Autodesk Fusion 360 part; units mm, degrees
(part 2 of 2)
ref_plane "WorkPlane7" through (0, 0, 8) normal (0, 0, 1) x (1, 0, 0) in component "07 Doorframe mounting platform - PRINT"
sketch "Case locating tab 2 outline" plane through (0, 0, 8) normal (0, 0, 1) x (1, 0, 0) in component "07 Doorframe mounting platform - PRINT"
  line L0 (112, 48.6) -> (132, 48.6)
  line L1 (132, 48.6) -> (132, 50)
  line L2 (132, 50) -> (112, 50)
  line L3 (112, 50) -> (112, 48.6)
extrude "Case locating tab 2" add sketch "Case locating tab 2 outline" along normal blind 6 bodies 22 in component "07 Doorframe mounting platform - PRINT"
ref_plane "WorkPlane8" through (0, 0, 8) normal (0, 0, 1) x (1, 0, 0) in component "07 Doorframe mounting platform - PRINT"
sketch "Case locating tab 3 outline" plane through (0, 0, 8) normal (0, 0, 1) x (1, 0, 0) in component "07 Doorframe mounting platform - PRINT"
  line L0 (10, -41.6) -> (30, -41.6)
  line L1 (30, -41.6) -> (30, -40.4)
  line L2 (30, -40.4) -> (10, -40.4)
  line L3 (10, -40.4) -> (10, -41.6)
extrude "Case locating tab 3" add sketch "Case locating tab 3 outline" along normal blind 6 bodies 22 in component "07 Doorframe mounting platform - PRINT"
ref_plane "WorkPlane9" through (0, 0, 8) normal (0, 0, 1) x (1, 0, 0) in component "07 Doorframe mounting platform - PRINT"
sketch "Case locating tab 4 outline" plane through (0, 0, 8) normal (0, 0, 1) x (1, 0, 0) in component "07 Doorframe mounting platform - PRINT"
  line L0 (112, -41.6) -> (132, -41.6)
  line L1 (132, -41.6) -> (132, -40.4)
  line L2 (132, -40.4) -> (112, -40.4)
  line L3 (112, -40.4) -> (112, -41.6)
extrude "Case locating tab 4" add sketch "Case locating tab 4 outline" along normal blind 6 bodies 22 in component "07 Doorframe mounting platform - PRINT"
ref_plane "WorkPlane10" through (0, 0, 8) normal (0, 0, 1) x (1, 0, 0) in component "07 Doorframe mounting platform - PRINT"
sketch "Case locating tab 5 outline" plane through (0, 0, 8) normal (0, 0, 1) x (1, 0, 0) in component "07 Doorframe mounting platform - PRINT"
  line L0 (-1.6, -30) -> (-0.4, -30)
  line L1 (-0.4, -30) -> (-0.4, -20)
  line L2 (-0.4, -20) -> (-1.6, -20)
  line L3 (-1.6, -20) -> (-1.6, -30)
extrude "Case locating tab 5" add sketch "Case locating tab 5 outline" along normal blind 6 bodies 22 in component "07 Doorframe mounting platform - PRINT"
ref_plane "WorkPlane11" through (0, 0, 8) normal (0, 0, 1) x (1, 0, 0) in component "07 Doorframe mounting platform - PRINT"
sketch "Case locating tab 6 outline" plane through (0, 0, 8) normal (0, 0, 1) x (1, 0, 0) in component "07 Doorframe mounting platform - PRINT"
  line L0 (-1.6, 28) -> (-0.4, 28)
  line L1 (-0.4, 28) -> (-0.4, 38)
  line L2 (-0.4, 38) -> (-1.6, 38)
  line L3 (-1.6, 38) -> (-1.6, 28)
extrude "Case locating tab 6" add sketch "Case locating tab 6 outline" along normal blind 6 bodies 22 in component "07 Doorframe mounting platform - PRINT"
ref_plane "WorkPlane12" through (0, 0, 8) normal (0, 0, 1) x (1, 0, 0) in component "07 Doorframe mounting platform - PRINT"
sketch "Case locating tab 7 outline" plane through (0, 0, 8) normal (0, 0, 1) x (1, 0, 0) in component "07 Doorframe mounting platform - PRINT"
  line L0 (142.4, -30) -> (143.6, -30)
  line L1 (143.6, -30) -> (143.6, -20)
  line L2 (143.6, -20) -> (142.4, -20)
  line L3 (142.4, -20) -> (142.4, -30)
extrude "Case locating tab 7" add sketch "Case locating tab 7 outline" along normal blind 6 bodies 22 in component "07 Doorframe mounting platform - PRINT"
ref_plane "WorkPlane13" through (0, 0, 8) normal (0, 0, 1) x (1, 0, 0) in component "07 Doorframe mounting platform - PRINT"
sketch "Case locating tab 8 outline" plane through (0, 0, 8) normal (0, 0, 1) x (1, 0, 0) in component "07 Doorframe mounting platform - PRINT"
  line L0 (142.4, 28) -> (143.6, 28)
  line L1 (143.6, 28) -> (143.6, 38)
  line L2 (143.6, 38) -> (142.4, 38)
  line L3 (142.4, 38) -> (142.4, 28)
extrude "Case locating tab 8" add sketch "Case locating tab 8 outline" along normal blind 6 bodies 22 in component "07 Doorframe mounting platform - PRINT"
ref_plane "WorkPlane14" through (0, 0, 1.9) normal (0, 0, 1) x (1, 0, 0) in component "07 Doorframe mounting platform - PRINT"
sketch "M4 long clamp bolt clearance layout" plane through (0, 0, 1.9) normal (0, 0, 1) x (1, 0, 0) in component "07 Doorframe mounting platform - PRINT"
  circle A0 centre (-10, -24) radius 2.25
  circle A1 centre (152, -24) radius 2.25
extrude "M4 long clamp bolt clearance" cut sketch "M4 long clamp bolt clearance layout" along normal blind 6.2 bodies 22 in component "07 Doorframe mounting platform - PRINT"
ref_plane "WorkPlane15" through (0, 0, 1.9) normal (0, 0, 1) x (1, 0, 0) in component "07 Doorframe mounting platform - PRINT"
sketch "M3 guide attachment clearance layout" plane through (0, 0, 1.9) normal (0, 0, 1) x (1, 0, 0) in component "07 Doorframe mounting platform - PRINT"
  circle A0 centre (-15, -8.5) radius 1.7
  circle A1 centre (-5, -8.5) radius 1.7
  circle A2 centre (147, -8.5) radius 1.7
  circle A3 centre (157, -8.5) radius 1.7
extrude "M3 guide attachment clearance" cut sketch "M3 guide attachment clearance layout" along normal blind 6.2 bodies 22 in component "07 Doorframe mounting platform - PRINT"
ref_plane "WorkPlane16" through (0, 0, 1.9) normal (0, 0, 1) x (1, 0, 0) in component "07 Doorframe mounting platform - PRINT"
sketch "Top-ledge rubber pad recesses layout" plane through (0, 0, 1.9) normal (0, 0, 1) x (1, 0, 0) in component "07 Doorframe mounting platform - PRINT"
  line L0 (-21, 2) -> (-1, 2)
  line L1 (-1, 2) -> (-1, 16)
  line L2 (-1, 16) -> (-21, 16)
  line L3 (-21, 16) -> (-21, 2)
  line L4 (-21, 33) -> (-1, 33)
  line L5 (-1, 33) -> (-1, 47)
  line L6 (-1, 47) -> (-21, 47)
  line L7 (-21, 47) -> (-21, 33)
  line L8 (143, 2) -> (163, 2)
  line L9 (163, 2) -> (163, 16)
  line L10 (163, 16) -> (143, 16)
  line L11 (143, 16) -> (143, 2)
  line L12 (143, 33) -> (163, 33)
  line L13 (163, 33) -> (163, 47)
  line L14 (163, 47) -> (143, 47)
  line L15 (143, 47) -> (143, 33)
extrude "Top-ledge rubber pad recesses" cut sketch "Top-ledge rubber pad recesses layout" along normal blind 0.6 bodies 22 in component "07 Doorframe mounting platform - PRINT"
ref_plane "WorkPlane1" through (0, 0, -53) normal (0, 0, 1) x (1, 0, 0) in component "08 left clamp guide - PRINT"
sketch "Guide beam outline" plane through (0, 0, -53) normal (0, 0, 1) x (1, 0, 0) in component "08 left clamp guide - PRINT"
  line L0 (-20, -11) -> (0, -11)
  line L1 (0, -11) -> (0, -6)
  line L2 (0, -6) -> (-20, -6)
  line L3 (-20, -6) -> (-20, -11)
extrude "Guide beam" add sketch "Guide beam outline" along normal blind 52 separate body makes body 23 in component "08 left clamp guide - PRINT"
ref_plane "WorkPlane2" through (0, 0, -1) normal (0, 0, 1) x (1, 0, 0) in component "08 left clamp guide - PRINT"
sketch "Guide mounting flange outline" plane through (0, 0, -1) normal (0, 0, 1) x (1, 0, 0) in component "08 left clamp guide - PRINT"
  line L0 (-23, -14) -> (3, -14)
  line L1 (3, -14) -> (3, -3)
  line L2 (3, -3) -> (-23, -3)
  line L3 (-23, -3) -> (-23, -14)
extrude "Guide mounting flange" add sketch "Guide mounting flange outline" along normal blind 3 bodies 23 in component "08 left clamp guide - PRINT"
ref_plane "WorkPlane3" through (0, 0, 2.1) normal (0, 0, 1) x (1, 0, 0) in component "08 left clamp guide - PRINT"
sketch "Two M3 guide pilots layout" plane through (0, 0, 2.1) normal (0, 0, 1) x (1, 0, 0) in component "08 left clamp guide - PRINT"
  circle A0 centre (-15, -8.5) radius 1.25
  circle A1 centre (-5, -8.5) radius 1.25
extrude "Two M3 guide pilots" cut sketch "Two M3 guide pilots layout" against normal blind 7.1 bodies 23 in component "08 left clamp guide - PRINT"
ref_plane "WorkPlane1" through (0, 0, -62) normal (0, 0, 1) x (1, 0, 0) in component "09 left sliding clamp jaw - PRINT"
sketch "Lower clamping jaw outline" plane through (0, 0, -62) normal (0, 0, 1) x (1, 0, 0) in component "09 left sliding clamp jaw - PRINT"
  line L0 (-23.35, -29) -> (3.35, -29)
  line L1 (3.35, -29) -> (3.35, 11.2)
  line L2 (3.35, 11.2) -> (-23.35, 11.2)
  line L3 (-23.35, 11.2) -> (-23.35, -29)
extrude "Lower clamping jaw" add sketch "Lower clamping jaw outline" along normal blind 5 separate body makes body 24 in component "09 left sliding clamp jaw - PRINT"
ref_plane "WorkPlane2" through (0, 0, -57) normal (0, 0, 1) x (1, 0, 0) in component "09 left sliding clamp jaw - PRINT"
sketch "Antirotation guide sleeve outline" plane through (0, 0, -57) normal (0, 0, 1) x (1, 0, 0) in component "09 left sliding clamp jaw - PRINT"
  line L0 (-23.35, -14.35) -> (3.35, -14.35)
  line L1 (3.35, -14.35) -> (3.35, -2.65)
  line L2 (3.35, -2.65) -> (-23.35, -2.65)
  line L3 (-23.35, -2.65) -> (-23.35, -14.35)
extrude "Antirotation guide sleeve" add sketch "Antirotation guide sleeve outline" along normal blind 16 bodies 24 in component "09 left sliding clamp jaw - PRINT"
ref_plane "WorkPlane3" through (0, 0, -57) normal (0, 0, 1) x (1, 0, 0) in component "09 left sliding clamp jaw - PRINT"
sketch "Sliding guide clearance outline" plane through (0, 0, -57) normal (0, 0, 1) x (1, 0, 0) in component "09 left sliding clamp jaw - PRINT"
  line L0 (-20.35, -11.35) -> (0.35, -11.35)
  line L1 (0.35, -11.35) -> (0.35, -5.65)
  line L2 (0.35, -5.65) -> (-20.35, -5.65)
  line L3 (-20.35, -5.65) -> (-20.35, -11.35)
extrude "Sliding guide clearance" cut sketch "Sliding guide clearance outline" along normal blind 16.1 bodies 24 in component "09 left sliding clamp jaw - PRINT"
ref_plane "WorkPlane4" through (0, 0, -62.1) normal (0, 0, 1) x (1, 0, 0) in component "09 left sliding clamp jaw - PRINT"
sketch "M4 long bolt clearance layout" plane through (0, 0, -62.1) normal (0, 0, 1) x (1, 0, 0) in component "09 left sliding clamp jaw - PRINT"
  circle A0 centre (-10, -24) radius 2.25
extrude "M4 long bolt clearance" cut sketch "M4 long bolt clearance layout" along normal blind 5.2 bodies 24 in component "09 left sliding clamp jaw - PRINT"
ref_plane "WorkPlane5" through (0, 0, -62.1) normal (0, 0, 1) x (1, 0, 0) in component "09 left sliding clamp jaw - PRINT"
sketch "Captive M4 nut outline" plane through (0, 0, -62.1) normal (0, 0, 1) x (1, 0, 0) in component "09 left sliding clamp jaw - PRINT"
  line L0 (-5.8431, -24) -> (-7.9215, -20.4)
  line L1 (-7.9215, -20.4) -> (-12.0785, -20.4)
  line L2 (-12.0785, -20.4) -> (-14.1569, -24)
  line L3 (-14.1569, -24) -> (-12.0785, -27.6)
  line L4 (-12.0785, -27.6) -> (-7.9215, -27.6)
  line L5 (-7.9215, -27.6) -> (-5.8431, -24)
extrude "Captive M4 nut" cut sketch "Captive M4 nut outline" along normal blind 3.5 bodies 24 in component "09 left sliding clamp jaw - PRINT"
ref_plane "WorkPlane6" through (0, 0, -57.5) normal (0, 0, 1) x (1, 0, 0) in component "09 left sliding clamp jaw - PRINT"
sketch "Jaw rubber pad recess layout" plane through (0, 0, -57.5) normal (0, 0, 1) x (1, 0, 0) in component "09 left sliding clamp jaw - PRINT"
  line L0 (-18, 1.5) -> (-2, 1.5)
  line L1 (-2, 1.5) -> (-2, 10.5)
  line L2 (-2, 10.5) -> (-18, 10.5)
  line L3 (-18, 10.5) -> (-18, 1.5)
extrude "Jaw rubber pad recess" cut sketch "Jaw rubber pad recess layout" along normal blind 0.6 bodies 24 in component "09 left sliding clamp jaw - PRINT"
ref_plane "WorkPlane1" through (0, 0, -53) normal (0, 0, 1) x (1, 0, 0) in component "08 right clamp guide - PRINT"
sketch "Guide beam outline (2)" plane through (0, 0, -53) normal (0, 0, 1) x (1, 0, 0) in component "08 right clamp guide - PRINT"
  line L0 (142, -11) -> (162, -11)
  line L1 (162, -11) -> (162, -6)
  line L2 (162, -6) -> (142, -6)
  line L3 (142, -6) -> (142, -11)
extrude "Guide beam'" add sketch "Guide beam outline (2)" along normal blind 52 separate body makes body 25 in component "08 right clamp guide - PRINT"
ref_plane "WorkPlane2" through (0, 0, -1) normal (0, 0, 1) x (1, 0, 0) in component "08 right clamp guide - PRINT"
sketch "Guide mounting flange outline (2)" plane through (0, 0, -1) normal (0, 0, 1) x (1, 0, 0) in component "08 right clamp guide - PRINT"
  line L0 (139, -14) -> (165, -14)
  line L1 (165, -14) -> (165, -3)
  line L2 (165, -3) -> (139, -3)
  line L3 (139, -3) -> (139, -14)
extrude "Guide mounting flange'" add sketch "Guide mounting flange outline (2)" along normal blind 3 bodies 25 in component "08 right clamp guide - PRINT"
ref_plane "WorkPlane3" through (0, 0, 2.1) normal (0, 0, 1) x (1, 0, 0) in component "08 right clamp guide - PRINT"
sketch "Two M3 guide pilots layout (2)" plane through (0, 0, 2.1) normal (0, 0, 1) x (1, 0, 0) in component "08 right clamp guide - PRINT"
  circle A0 centre (147, -8.5) radius 1.25
  circle A1 centre (157, -8.5) radius 1.25
extrude "Two M3 guide pilots'" cut sketch "Two M3 guide pilots layout (2)" against normal blind 7.1 bodies 25 in component "08 right clamp guide - PRINT"
ref_plane "WorkPlane1" through (0, 0, -62) normal (0, 0, 1) x (1, 0, 0) in component "09 right sliding clamp jaw - PRINT"
sketch "Lower clamping jaw outline (2)" plane through (0, 0, -62) normal (0, 0, 1) x (1, 0, 0) in component "09 right sliding clamp jaw - PRINT"
  line L0 (138.65, -29) -> (165.35, -29)
  line L1 (165.35, -29) -> (165.35, 11.2)
  line L2 (165.35, 11.2) -> (138.65, 11.2)
  line L3 (138.65, 11.2) -> (138.65, -29)
extrude "Lower clamping jaw'" add sketch "Lower clamping jaw outline (2)" along normal blind 5 separate body makes body 26 in component "09 right sliding clamp jaw - PRINT"
ref_plane "WorkPlane2" through (0, 0, -57) normal (0, 0, 1) x (1, 0, 0) in component "09 right sliding clamp jaw - PRINT"
sketch "Antirotation guide sleeve outline (2)" plane through (0, 0, -57) normal (0, 0, 1) x (1, 0, 0) in component "09 right sliding clamp jaw - PRINT"
  line L0 (138.65, -14.35) -> (165.35, -14.35)
  line L1 (165.35, -14.35) -> (165.35, -2.65)
  line L2 (165.35, -2.65) -> (138.65, -2.65)
  line L3 (138.65, -2.65) -> (138.65, -14.35)
extrude "Antirotation guide sleeve'" add sketch "Antirotation guide sleeve outline (2)" along normal blind 16 bodies 26 in component "09 right sliding clamp jaw - PRINT"
ref_plane "WorkPlane3" through (0, 0, -57) normal (0, 0, 1) x (1, 0, 0) in component "09 right sliding clamp jaw - PRINT"
sketch "Sliding guide clearance outline (2)" plane through (0, 0, -57) normal (0, 0, 1) x (1, 0, 0) in component "09 right sliding clamp jaw - PRINT"
  line L0 (141.65, -11.35) -> (162.35, -11.35)
  line L1 (162.35, -11.35) -> (162.35, -5.65)
  line L2 (162.35, -5.65) -> (141.65, -5.65)
  line L3 (141.65, -5.65) -> (141.65, -11.35)
extrude "Sliding guide clearance'" cut sketch "Sliding guide clearance outline (2)" along normal blind 16.1 bodies 26 in component "09 right sliding clamp jaw - PRINT"
ref_plane "WorkPlane4" through (0, 0, -62.1) normal (0, 0, 1) x (1, 0, 0) in component "09 right sliding clamp jaw - PRINT"
sketch "M4 long bolt clearance layout (2)" plane through (0, 0, -62.1) normal (0, 0, 1) x (1, 0, 0) in component "09 right sliding clamp jaw - PRINT"
  circle A0 centre (152, -24) radius 2.25
extrude "M4 long bolt clearance'" cut sketch "M4 long bolt clearance layout (2)" along normal blind 5.2 bodies 26 in component "09 right sliding clamp jaw - PRINT"
ref_plane "WorkPlane5" through (0, 0, -62.1) normal (0, 0, 1) x (1, 0, 0) in component "09 right sliding clamp jaw - PRINT"
sketch "Captive M4 nut outline (2)" plane through (0, 0, -62.1) normal (0, 0, 1) x (1, 0, 0) in component "09 right sliding clamp jaw - PRINT"
  line L0 (156.1569, -24) -> (154.0785, -20.4)
  line L1 (154.0785, -20.4) -> (149.9215, -20.4)
  line L2 (149.9215, -20.4) -> (147.8431, -24)
  line L3 (147.8431, -24) -> (149.9215, -27.6)
  line L4 (149.9215, -27.6) -> (154.0785, -27.6)
  line L5 (154.0785, -27.6) -> (156.1569, -24)
extrude "Captive M4 nut'" cut sketch "Captive M4 nut outline (2)" along normal blind 3.5 bodies 26 in component "09 right sliding clamp jaw - PRINT"
ref_plane "WorkPlane6" through (0, 0, -57.5) normal (0, 0, 1) x (1, 0, 0) in component "09 right sliding clamp jaw - PRINT"
sketch "Jaw rubber pad recess layout (2)" plane through (0, 0, -57.5) normal (0, 0, 1) x (1, 0, 0) in component "09 right sliding clamp jaw - PRINT"
  line L0 (144, 1.5) -> (160, 1.5)
  line L1 (160, 1.5) -> (160, 10.5)
  line L2 (160, 10.5) -> (144, 10.5)
  line L3 (144, 10.5) -> (144, 1.5)
extrude "Jaw rubber pad recess'" cut sketch "Jaw rubber pad recess layout (2)" along normal blind 0.6 bodies 26 in component "09 right sliding clamp jaw - PRINT"
sketch "Top-ledge pad 1 - nominal 3 mm foam outline" plane through (0, 0, 0) normal (0, 0, 1) x (1, 0, 0) in component "REFERENCE - six compressed mount rubber pads"
  line L0 (-21, 2) -> (-1, 2)
  line L1 (-1, 2) -> (-1, 16)
  line L2 (-1, 16) -> (-21, 16)
  line L3 (-21, 16) -> (-21, 2)
extrude "Top-ledge pad 1 - nominal 3 mm foam" add sketch "Top-ledge pad 1 - nominal 3 mm foam outline" along normal blind 2.5 separate body makes body 27 in component "REFERENCE - six compressed mount rubber pads"
sketch "Top-ledge pad 2 - nominal 3 mm foam outline" plane through (0, 0, 0) normal (0, 0, 1) x (1, 0, 0) in component "REFERENCE - six compressed mount rubber pads"
  line L0 (-21, 33) -> (-1, 33)
  line L1 (-1, 33) -> (-1, 47)
  line L2 (-1, 47) -> (-21, 47)
  line L3 (-21, 47) -> (-21, 33)
extrude "Top-ledge pad 2 - nominal 3 mm foam" add sketch "Top-ledge pad 2 - nominal 3 mm foam outline" along normal blind 2.5 separate body makes body 28 in component "REFERENCE - six compressed mount rubber pads"
sketch "Top-ledge pad 3 - nominal 3 mm foam outline" plane through (0, 0, 0) normal (0, 0, 1) x (1, 0, 0) in component "REFERENCE - six compressed mount rubber pads"
  line L0 (143, 2) -> (163, 2)
  line L1 (163, 2) -> (163, 16)
  line L2 (163, 16) -> (143, 16)
  line L3 (143, 16) -> (143, 2)
extrude "Top-ledge pad 3 - nominal 3 mm foam" add sketch "Top-ledge pad 3 - nominal 3 mm foam outline" along normal blind 2.5 separate body makes body 29 in component "REFERENCE - six compressed mount rubber pads"
sketch "Top-ledge pad 4 - nominal 3 mm foam outline" plane through (0, 0, 0) normal (0, 0, 1) x (1, 0, 0) in component "REFERENCE - six compressed mount rubber pads"
  line L0 (143, 33) -> (163, 33)
  line L1 (163, 33) -> (163, 47)
  line L2 (163, 47) -> (143, 47)
  line L3 (143, 47) -> (143, 33)
extrude "Top-ledge pad 4 - nominal 3 mm foam" add sketch "Top-ledge pad 4 - nominal 3 mm foam outline" along normal blind 2.5 separate body makes body 30 in component "REFERENCE - six compressed mount rubber pads"
ref_plane "WorkPlane1" through (0, 0, -57.5) normal (0, 0, 1) x (1, 0, 0) in component "REFERENCE - six compressed mount rubber pads"
sketch "left underside pad - nominal 3 mm foam outline" plane through (0, 0, -57.5) normal (0, 0, 1) x (1, 0, 0) in component "REFERENCE - six compressed mount rubber pads"
  line L0 (-18, 1.5) -> (-2, 1.5)
  line L1 (-2, 1.5) -> (-2, 10.5)
  line L2 (-2, 10.5) -> (-18, 10.5)
  line L3 (-18, 10.5) -> (-18, 1.5)
extrude "left underside pad - nominal 3 mm foam" add sketch "left underside pad - nominal 3 mm foam outline" along normal blind 2.5 separate body makes body 31 in component "REFERENCE - six compressed mount rubber pads"
ref_plane "WorkPlane2" through (0, 0, -57.5) normal (0, 0, 1) x (1, 0, 0) in component "REFERENCE - six compressed mount rubber pads"
sketch "right underside pad - nominal 3 mm foam outline" plane through (0, 0, -57.5) normal (0, 0, 1) x (1, 0, 0) in component "REFERENCE - six compressed mount rubber pads"
  line L0 (144, 1.5) -> (160, 1.5)
  line L1 (160, 1.5) -> (160, 10.5)
  line L2 (160, 10.5) -> (144, 10.5)
  line L3 (144, 10.5) -> (144, 1.5)
extrude "right underside pad - nominal 3 mm foam" add sketch "right underside pad - nominal 3 mm foam outline" along normal blind 2.5 separate body makes body 32 in component "REFERENCE - six compressed mount rubber pads"
ref_plane "WorkPlane1" through (-30, 0, 0) normal (1, 0, 0) x (0, 1, 0) in component "REFERENCE - measured doorframe profile - assumed orientation"
sketch "52 overhang - 55 lip - 12 inset - 12 x 11 step profile" plane through (-30, 0, 0) normal (1, 0, 0) x (0, 0, -1) in component "REFERENCE - measured doorframe profile - assumed orientation"
  line L0 (0, 0) -> (0, 52)
  line L1 (0, 52) -> (90, 52)
  line L2 (90, 52) -> (90, 23)
  line L3 (90, 23) -> (67, 23)
  line L4 (67, 23) -> (67, 12)
  line L5 (67, 12) -> (55, 12)
  line L6 (55, 12) -> (55, 0)
  line L7 (55, 0) -> (0, 0)
extrude "52 overhang - 55 lip - 12 inset - 12 x 11 step" add sketch "52 overhang - 55 lip - 12 inset - 12 x 11 step profile" along normal blind 202 separate body makes body 33 in component "REFERENCE - measured doorframe profile - assumed orientation"
ref_plane "WorkPlane1" through (225, 0, 0) normal (1, 0, 0) x (0, 1, 0) in component "10 Doorframe fit gauge PRINT FIRST - PRINT"
sketch "Stepped profile gauge - 0.6 mm clearance profile" plane through (225, 0, 0) normal (1, 0, 0) x (0, 0, -1) in component "10 Doorframe fit gauge PRINT FIRST - PRINT"
  line L0 (-0.6, 52) -> (-0.6, -0.6)
  line L1 (-0.6, -0.6) -> (55.6, -0.6)
  line L2 (55.6, -0.6) -> (55.6, 11.4)
  line L3 (55.6, 11.4) -> (67.6, 11.4)
  line L4 (67.6, 11.4) -> (67.6, 23)
  line L5 (67.6, 23) -> (70, 23)
  line L6 (70, 23) -> (70, 9)
  line L7 (70, 9) -> (58, 9)
  line L8 (58, 9) -> (58, -3)
  line L9 (58, -3) -> (-3, -3)
  line L10 (-3, -3) -> (-3, 52)
  line L11 (-3, 52) -> (-0.6, 52)
extrude "Stepped profile gauge - 0.6 mm clearance" add sketch "Stepped profile gauge - 0.6 mm clearance profile" along normal blind 8 separate body makes body 34 in component "10 Doorframe fit gauge PRINT FIRST - PRINT"
ref_plane "WorkPlane1" through (0, 0, -62) normal (0, 0, 1) x (1, 0, 0) in component "REFERENCE - M4 mount fasteners - smooth envelopes"
sketch "left clamp nut hexagon" plane through (0, 0, -62) normal (0, 0, 1) x (1, 0, 0) in component "REFERENCE - M4 mount fasteners - smooth envelopes"
  line L0 (-5.9585, -24) -> (-7.9793, -20.5)
  line L1 (-7.9793, -20.5) -> (-12.0207, -20.5)
  line L2 (-12.0207, -20.5) -> (-14.0415, -24)
  line L3 (-14.0415, -24) -> (-12.0207, -27.5)
  line L4 (-12.0207, -27.5) -> (-7.9793, -27.5)
  line L5 (-7.9793, -27.5) -> (-5.9585, -24)
extrude "left clamp nut" add sketch "left clamp nut hexagon" along normal blind 3.2 separate body makes body 35 in component "REFERENCE - M4 mount fasteners - smooth envelopes"
ref_plane "WorkPlane2" through (0, 0, -62.1) normal (0, 0, 1) x (1, 0, 0) in component "REFERENCE - M4 mount fasteners - smooth envelopes"
sketch "left clamp nut bore layout" plane through (0, 0, -62.1) normal (0, 0, 1) x (1, 0, 0) in component "REFERENCE - M4 mount fasteners - smooth envelopes"
  circle A0 centre (-10, -24) radius 2.1
extrude "left clamp nut bore" cut sketch "left clamp nut bore layout" along normal blind 3.4 bodies 35 in component "REFERENCE - M4 mount fasteners - smooth envelopes"
ref_plane "WorkPlane3" through (0, 0, 8) normal (0, 0, 1) x (1, 0, 0) in component "REFERENCE - M4 mount fasteners - smooth envelopes"
sketch "left washer layout" plane through (0, 0, 8) normal (0, 0, 1) x (1, 0, 0) in component "REFERENCE - M4 mount fasteners - smooth envelopes"
  circle A0 centre (-10, -24) radius 4.5
extrude "left washer" add sketch "left washer layout" along normal blind 0.8 separate body makes body 36 in component "REFERENCE - M4 mount fasteners - smooth envelopes"
ref_plane "WorkPlane4" through (0, 0, 7.9) normal (0, 0, 1) x (1, 0, 0) in component "REFERENCE - M4 mount fasteners - smooth envelopes"
sketch "left washer bore layout" plane through (0, 0, 7.9) normal (0, 0, 1) x (1, 0, 0) in component "REFERENCE - M4 mount fasteners - smooth envelopes"
  circle A0 centre (-10, -24) radius 2.1
extrude "left washer bore" cut sketch "left washer bore layout" along normal blind 1 bodies 35 36 in component "REFERENCE - M4 mount fasteners - smooth envelopes"
ref_plane "WorkPlane5" through (0, 0, -71.2) normal (0, 0, 1) x (1, 0, 0) in component "REFERENCE - M4 mount fasteners - smooth envelopes"
sketch "left M4 x 80 shank layout" plane through (0, 0, -71.2) normal (0, 0, 1) x (1, 0, 0) in component "REFERENCE - M4 mount fasteners - smooth envelopes"
  circle A0 centre (-10, -24) radius 2
extrude "left M4 x 80 shank" add sketch "left M4 x 80 shank layout" along normal blind 80 separate body makes body 37 in component "REFERENCE - M4 mount fasteners - smooth envelopes"
ref_plane "WorkPlane6" through (0, 0, 8.8) normal (0, 0, 1) x (1, 0, 0) in component "REFERENCE - M4 mount fasteners - smooth envelopes"
sketch "left clamp screw head layout" plane through (0, 0, 8.8) normal (0, 0, 1) x (1, 0, 0) in component "REFERENCE - M4 mount fasteners - smooth envelopes"
  circle A0 centre (-10, -24) radius 3.5
extrude "left clamp screw head" add sketch "left clamp screw head layout" along normal blind 4 bodies 36 37 in component "REFERENCE - M4 mount fasteners - smooth envelopes"
ref_plane "WorkPlane7" through (0, 0, -62) normal (0, 0, 1) x (1, 0, 0) in component "REFERENCE - M4 mount fasteners - smooth envelopes"
sketch "right clamp nut hexagon" plane through (0, 0, -62) normal (0, 0, 1) x (1, 0, 0) in component "REFERENCE - M4 mount fasteners - smooth envelopes"
  line L0 (156.0415, -24) -> (154.0207, -20.5)
  line L1 (154.0207, -20.5) -> (149.9793, -20.5)
  line L2 (149.9793, -20.5) -> (147.9585, -24)
  line L3 (147.9585, -24) -> (149.9793, -27.5)
  line L4 (149.9793, -27.5) -> (154.0207, -27.5)
  line L5 (154.0207, -27.5) -> (156.0415, -24)
extrude "right clamp nut" add sketch "right clamp nut hexagon" along normal blind 3.2 separate body makes body 38 in component "REFERENCE - M4 mount fasteners - smooth envelopes"
ref_plane "WorkPlane8" through (0, 0, -62.1) normal (0, 0, 1) x (1, 0, 0) in component "REFERENCE - M4 mount fasteners - smooth envelopes"
sketch "right clamp nut bore layout" plane through (0, 0, -62.1) normal (0, 0, 1) x (1, 0, 0) in component "REFERENCE - M4 mount fasteners - smooth envelopes"
  circle A0 centre (152, -24) radius 2.1
extrude "right clamp nut bore" cut sketch "right clamp nut bore layout" along normal blind 3.4 bodies 35 36 38 in component "REFERENCE - M4 mount fasteners - smooth envelopes"
ref_plane "WorkPlane9" through (0, 0, 8) normal (0, 0, 1) x (1, 0, 0) in component "REFERENCE - M4 mount fasteners - smooth envelopes"
sketch "right washer layout" plane through (0, 0, 8) normal (0, 0, 1) x (1, 0, 0) in component "REFERENCE - M4 mount fasteners - smooth envelopes"
  circle A0 centre (152, -24) radius 4.5
extrude "right washer" add sketch "right washer layout" along normal blind 0.8 separate body makes body 39 in component "REFERENCE - M4 mount fasteners - smooth envelopes"
ref_plane "WorkPlane10" through (0, 0, 7.9) normal (0, 0, 1) x (1, 0, 0) in component "REFERENCE - M4 mount fasteners - smooth envelopes"
sketch "right washer bore layout" plane through (0, 0, 7.9) normal (0, 0, 1) x (1, 0, 0) in component "REFERENCE - M4 mount fasteners - smooth envelopes"
  circle A0 centre (152, -24) radius 2.1
extrude "right washer bore" cut sketch "right washer bore layout" along normal blind 1 bodies 35 36 38 39 in component "REFERENCE - M4 mount fasteners - smooth envelopes"
ref_plane "WorkPlane11" through (0, 0, -71.2) normal (0, 0, 1) x (1, 0, 0) in component "REFERENCE - M4 mount fasteners - smooth envelopes"
sketch "right M4 x 80 shank layout" plane through (0, 0, -71.2) normal (0, 0, 1) x (1, 0, 0) in component "REFERENCE - M4 mount fasteners - smooth envelopes"
  circle A0 centre (152, -24) radius 2
extrude "right M4 x 80 shank" add sketch "right M4 x 80 shank layout" along normal blind 80 separate body makes body 40 in component "REFERENCE - M4 mount fasteners - smooth envelopes"
ref_plane "WorkPlane12" through (0, 0, 8.8) normal (0, 0, 1) x (1, 0, 0) in component "REFERENCE - M4 mount fasteners - smooth envelopes"
sketch "right clamp screw head layout" plane through (0, 0, 8.8) normal (0, 0, 1) x (1, 0, 0) in component "REFERENCE - M4 mount fasteners - smooth envelopes"
  circle A0 centre (152, -24) radius 3.5
extrude "right clamp screw head" add sketch "right clamp screw head layout" along normal blind 4 bodies 39 40 in component "REFERENCE - M4 mount fasteners - smooth envelopes"
ref_plane "WorkPlane13" through (0, 0, 3) normal (0, 0, 1) x (1, 0, 0) in component "REFERENCE - M4 mount fasteners - smooth envelopes"
sketch "Case nut 0 hexagon" plane through (0, 0, 3) normal (0, 0, 1) x (1, 0, 0) in component "REFERENCE - M4 mount fasteners - smooth envelopes"
  line L0 (136.0415, -14) -> (134.0207, -10.5)
  line L1 (134.0207, -10.5) -> (129.9793, -10.5)
  line L2 (129.9793, -10.5) -> (127.9585, -14)
  line L3 (127.9585, -14) -> (129.9793, -17.5)
  line L4 (129.9793, -17.5) -> (134.0207, -17.5)
  line L5 (134.0207, -17.5) -> (136.0415, -14)
extrude "Case nut 0" add sketch "Case nut 0 hexagon" along normal blind 3.2 separate body makes body 41 in component "REFERENCE - M4 mount fasteners - smooth envelopes"
ref_plane "WorkPlane14" through (0, 0, 2.9) normal (0, 0, 1) x (1, 0, 0) in component "REFERENCE - M4 mount fasteners - smooth envelopes"
sketch "Case nut 0 bore layout" plane through (0, 0, 2.9) normal (0, 0, 1) x (1, 0, 0) in component "REFERENCE - M4 mount fasteners - smooth envelopes"
  circle A0 centre (132, -14) radius 2.1
extrude "Case nut 0 bore" cut sketch "Case nut 0 bore layout" along normal blind 3.4 bodies 35 36 38 39 41 in component "REFERENCE - M4 mount fasteners - smooth envelopes"
ref_plane "WorkPlane15" through (0, 0, 2.6) normal (0, 0, 1) x (1, 0, 0) in component "REFERENCE - M4 mount fasteners - smooth envelopes"
sketch "Case M4 x 10 shank 0 layout" plane through (0, 0, 2.6) normal (0, 0, 1) x (1, 0, 0) in component "REFERENCE - M4 mount fasteners - smooth envelopes"
  circle A0 centre (132, -14) radius 2
extrude "Case M4 x 10 shank 0" add sketch "Case M4 x 10 shank 0 layout" along normal blind 10 separate body makes body 42 in component "REFERENCE - M4 mount fasteners - smooth envelopes"
ref_plane "WorkPlane16" through (0, 0, 12.6) normal (0, 0, 1) x (1, 0, 0) in component "REFERENCE - M4 mount fasteners - smooth envelopes"
sketch "Case screw head 0 layout" plane through (0, 0, 12.6) normal (0, 0, 1) x (1, 0, 0) in component "REFERENCE - M4 mount fasteners - smooth envelopes"
  circle A0 centre (132, -14) radius 3.5
extrude "Case screw head 0" add sketch "Case screw head 0 layout" along normal blind 2.8 bodies 42 in component "REFERENCE - M4 mount fasteners - smooth envelopes"
ref_plane "WorkPlane17" through (0, 0, 3) normal (0, 0, 1) x (1, 0, 0) in component "REFERENCE - M4 mount fasteners - smooth envelopes"
sketch "Case nut 1 hexagon" plane through (0, 0, 3) normal (0, 0, 1) x (1, 0, 0) in component "REFERENCE - M4 mount fasteners - smooth envelopes"
  line L0 (136.0415, 22) -> (134.0207, 25.5)
  line L1 (134.0207, 25.5) -> (129.9793, 25.5)
  line L2 (129.9793, 25.5) -> (127.9585, 22)
  line L3 (127.9585, 22) -> (129.9793, 18.5)
  line L4 (129.9793, 18.5) -> (134.0207, 18.5)
  line L5 (134.0207, 18.5) -> (136.0415, 22)
extrude "Case nut 1" add sketch "Case nut 1 hexagon" along normal blind 3.2 separate body makes body 43 in component "REFERENCE - M4 mount fasteners - smooth envelopes"
ref_plane "WorkPlane18" through (0, 0, 2.9) normal (0, 0, 1) x (1, 0, 0) in component "REFERENCE - M4 mount fasteners - smooth envelopes"
sketch "Case nut 1 bore layout" plane through (0, 0, 2.9) normal (0, 0, 1) x (1, 0, 0) in component "REFERENCE - M4 mount fasteners - smooth envelopes"
  circle A0 centre (132, 22) radius 2.1
extrude "Case nut 1 bore" cut sketch "Case nut 1 bore layout" along normal blind 3.4 bodies 35 36 38 39 41 42 43 in component "REFERENCE - M4 mount fasteners - smooth envelopes"
ref_plane "WorkPlane19" through (0, 0, 2.6) normal (0, 0, 1) x (1, 0, 0) in component "REFERENCE - M4 mount fasteners - smooth envelopes"
sketch "Case M4 x 10 shank 1 layout" plane through (0, 0, 2.6) normal (0, 0, 1) x (1, 0, 0) in component "REFERENCE - M4 mount fasteners - smooth envelopes"
  circle A0 centre (132, 22) radius 2
extrude "Case M4 x 10 shank 1" add sketch "Case M4 x 10 shank 1 layout" along normal blind 10 separate body makes body 44 in component "REFERENCE - M4 mount fasteners - smooth envelopes"
ref_plane "WorkPlane20" through (0, 0, 12.6) normal (0, 0, 1) x (1, 0, 0) in component "REFERENCE - M4 mount fasteners - smooth envelopes"
sketch "Case screw head 1 layout" plane through (0, 0, 12.6) normal (0, 0, 1) x (1, 0, 0) in component "REFERENCE - M4 mount fasteners - smooth envelopes"
  circle A0 centre (132, 22) radius 3.5
extrude "Case screw head 1" add sketch "Case screw head 1 layout" along normal blind 2.8 bodies 44 in component "REFERENCE - M4 mount fasteners - smooth envelopes"
component "01 Battery tray - PRINT" placed x (1, 0, 0) y (0, 1, 0) z (0, 0, 1) at (0, -40, 10.2)
component "02 Pi tray and upper shell - PRINT" placed x (1, 0, 0) y (0, 1, 0) z (0, 0, 1) at (0, -40, 10.2)
component "03 Vented lid - PRINT" placed x (1, 0, 0) y (0, 1, 0) z (0, 0, 1) at (0, -40, 10.2)
component "REFERENCE - INIU P51L-E2 115 x 73 x 29 mm" placed x (1, 0, 0) y (0, 1, 0) z (0, 0, 1) at (0, -40, 10.2)
component "REFERENCE - Raspberry Pi4 rotated ports" placed x (1, 0, 0) y (0, 1, 0) z (0, 0, 1) at (0, -40, 10.2)
component "REFERENCE - four 20 x 10 x 3 mm rubber pads" placed x (1, 0, 0) y (0, 1, 0) z (0, 0, 1) at (0, -40, 10.2)
component "04 Camera G carrier - PRINT" placed x (1, 0, 0) y (0, -0.707107, 0.707107) z (0, -0.707107, -0.707107) at (52, -40.5, 47.2)
component "05 Camera G protective cap - PRINT" placed x (1, 0, 0) y (0, -0.707107, 0.707107) z (0, -0.707107, -0.707107) at (52, -40.5, 47.2)
component "REFERENCE - Waveshare RPi Camera G PCB and lens" placed x (1, 0, 0) y (0, -0.707107, 0.707107) z (0, -0.707107, -0.707107) at (52, -40.5, 47.2)
component "06 Camera 45 degree bracket - PRINT - provisional aim" placed x (1, 0, 0) y (0, -0.707107, 0.707107) z (0, -0.707107, -0.707107) at (52, -40.5, 47.2)
component "07 Doorframe mounting platform - PRINT" placed x (1, 0, 0) y (0, 1, 0) z (0, 0, 1) at (0, 0, 0)
component "08 left clamp guide - PRINT" placed x (1, 0, 0) y (0, 1, 0) z (0, 0, 1) at (0, 0, 0)
component "09 left sliding clamp jaw - PRINT" placed x (1, 0, 0) y (0, 1, 0) z (0, 0, 1) at (0, 0, 0)
component "08 right clamp guide - PRINT" placed x (1, 0, 0) y (0, 1, 0) z (0, 0, 1) at (0, 0, 0)
component "09 right sliding clamp jaw - PRINT" placed x (1, 0, 0) y (0, 1, 0) z (0, 0, 1) at (0, 0, 0)
component "REFERENCE - six compressed mount rubber pads" placed x (1, 0, 0) y (0, 1, 0) z (0, 0, 1) at (0, 0, 0)
component "REFERENCE - measured doorframe profile - assumed orientation" placed x (1, 0, 0) y (0, 1, 0) z (0, 0, 1) at (0, 0, 0)
component "10 Doorframe fit gauge PRINT FIRST - PRINT" placed x (1, 0, 0) y (0, 1, 0) z (0, 0, 1) at (0, 0, 0)
component "REFERENCE - M4 mount fasteners - smooth envelopes" placed x (1, 0, 0) y (0, 1, 0) z (0, 0, 1) at (0, 0, 0)
equation "wall = 2.4 mm" comment "Printed shell wall and tray thickness"
equation "battery_tray_height = 37 mm" comment "Battery chamber outside height"
equation "upper_height = 32 mm" comment "Pi chamber height above battery tray"
equation "lid_thickness = 2.4 mm" comment "Removable lid"
equation "pi_standoff_height = 5 mm" comment "Pi underside clearance"
equation "pad_recess_depth = 0.8 mm" comment "Use 3 mm rubber pads; 2.2 mm projects below case"
equation "camera_carrier_thickness = 3 mm" comment "Camera backplate"
equation "camera_standoff_height = 2.5 mm" comment "Clearance under camera PCB"
equation "camera_lens_opening = 22 mm" comment "Generous opening; check actual lens barrel before final print"
equation "camera_cap_height = 17 mm" comment "Cap height above carrier; lens must project beyond the front"
equation "d11 = battery_tray_height"
equation "d27 = pad_recess_depth"
equation "d49 = upper_height"
equation "d65 = pi_standoff_height"
equation "d95 = lid_thickness"
equation "d177 = camera_carrier_thickness"
equation "d181 = camera_standoff_height"
equation "d193 = camera_cap_height"
equation "d201 = camera_lens_opening"
equation "frame_overhang = 52 mm" comment "Confirmed ledge width; positive Y points toward door"
equation "frame_lip_height = 55 mm" comment "Confirmed first vertical face height"
equation "frame_inset = 12 mm" comment "Confirmed first underside return"
equation "frame_step_height = 12 mm" comment "Confirmed second vertical step"
equation "frame_step_width = 11 mm" comment "Confirmed second underside return"
equation "frame_fit_clearance = 0.6 mm" comment "Gauge clearance; documentation parameter"
equation "jaw_slide_clearance = 0.35 mm" comment "Clearance per guide side; documentation parameter"
named bodies: "Battery tray shell", "Upper shell", "Lid", "INIU envelope - check supplied cable position", "Pi PCB 85 x 56 x 1.6", "USB3", "USB2", "Ethernet", "USB-C", "HDMI0", "HDMI1", "Audio", "Rubber pad 1", "Rubber pad 2", "Rubber pad 3", "Rubber pad 4", "Camera carrier", "Camera cap shell", "Camera PCB 25 x 24", "Six mm platform", "Guide beam", "Lower clamping jaw", "Top-ledge pad 1 - nominal 3 mm foam", "Top-ledge pad 2 - nominal 3 mm foam", "Top-ledge pad 3 - nominal 3 mm foam", "Top-ledge pad 4 - nominal 3 mm foam", "left underside pad - nominal 3 mm foam", "right underside pad - nominal 3 mm foam"
